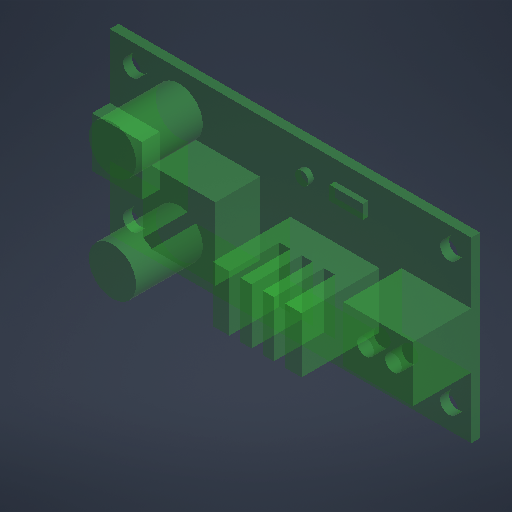
# Autodesk Inventor part: Power_Supply_Module
Saved by Autodesk Inventor 2027.1 (Build 311270010, 270A)
## iProperties
Part Number: Power_Supply_Module
Material: Generic
Document SubType Name: Modeling
Designer: austin
Appearance: Green
Author: austin
Autodesk Inventor part; units mm, degrees
sketch "Sketch1" plane through (0, 0, 0) normal (0, 0, 1) x (1, 0, 0)
  line L0 (-32.5, -16) -> (32.5, -16)
  line L1 (32.5, -16) -> (32.5, 16)
  line L2 (32.5, 16) -> (-32.5, 16)
  line L3 (-32.5, 16) -> (-32.5, -16)
  constraints: 8 end point, 2 parallel, 1 horizontal, 1 perpendicular
extrude "Extrusion1" add sketch "Sketch1" along normal blind 1.6
sketch "Sketch2" plane through (0, 0, 0) normal (0, 0, 1) x (1, 0, 0)
  circle A0 centre (-28.5, -12) radius 1.6
  circle A1 centre (28.5, -12) radius 1.6
  circle A2 centre (-28.5, 12) radius 1.6
  circle A3 centre (28.5, 12) radius 1.6
  constraints: 4 centre point
extrude "Extrusion2" cut sketch "Sketch2" along normal blind 2
ref_plane "Work Plane1" through (0, 0, 1.6) normal (0, 0, 1) x (1, 0, 0)
sketch "Sketch3" plane through (0, 0, 1.6) normal (0, 0, 1) x (1, 0, 0)
  line L0 (-32.5, -4.5) -> (-23.5, -4.5)
  line L1 (-23.5, -4.5) -> (-23.5, 4.5)
  line L2 (-23.5, 4.5) -> (-32.5, 4.5)
  line L3 (-32.5, 4.5) -> (-32.5, -4.5)
  constraints: 8 end point, 2 parallel, 1 horizontal, 1 perpendicular
extrude "Extrusion3" add sketch "Sketch3" along normal blind 3.2
sketch "Sketch4" plane through (0, 0, 1.6) normal (0, 0, 1) x (1, 0, 0)
  line L0 (-18.5, -6.5) -> (-5.5, -6.5)
  line L1 (-5.5, -6.5) -> (-5.5, 6.5)
  line L2 (-5.5, 6.5) -> (-18.5, 6.5)
  line L3 (-18.5, 6.5) -> (-18.5, -6.5)
  constraints: 8 end point, 2 parallel, 1 horizontal, 1 perpendicular
extrude "Extrusion4" add sketch "Sketch4" along normal blind 8
sketch "Sketch5" plane through (0, 0, 1.6) normal (0, 0, 1) x (1, 0, 0)
  circle A0 centre (-20, -9.5) radius 4.25
  circle A1 centre (-20, 9.5) radius 4.25
  constraints: 2 centre point
extrude "Extrusion5" add sketch "Sketch5" along normal blind 12
sketch "Sketch6" plane through (0, 0, 1.6) normal (0, 0, 1) x (1, 0, 0)
  line L0 (0, -7) -> (16, -7)
  line L1 (16, -7) -> (16, 3)
  line L2 (16, 3) -> (0, 3)
  line L3 (0, 3) -> (0, -7)
  constraints: 8 end point, 2 parallel, 1 horizontal, 1 perpendicular
extrude "Extrusion6" add sketch "Sketch6" along normal blind 14
ref_plane "Work Plane2" through (0, 0, 15.6) normal (0, 0, 1) x (1, 0, 0)
sketch "Sketch7" plane through (0, 0, 15.6) normal (0, 0, 1) x (1, 0, 0)
  line L0 (3, -7) -> (5, -7)
  line L1 (5, -7) -> (5, 3)
  line L2 (5, 3) -> (3, 3)
  line L3 (3, 3) -> (3, -7)
  line L4 (7, -7) -> (9, -7)
  line L5 (9, -7) -> (9, 3)
  line L6 (9, 3) -> (7, 3)
  line L7 (7, 3) -> (7, -7)
  line L8 (11, -7) -> (13, -7)
  line L9 (13, -7) -> (13, 3)
  line L10 (13, 3) -> (11, 3)
  line L11 (11, 3) -> (11, -7)
  constraints: 24 end point, 6 parallel, 3 horizontal, 3 perpendicular
extrude "Extrusion7" cut sketch "Sketch7" against normal blind 9
sketch "Sketch8" plane through (0, 0, 1.6) normal (0, 0, 1) x (1, 0, 0)
  line L0 (20, -5) -> (32.5, -5)
  line L1 (32.5, -5) -> (32.5, 5)
  line L2 (32.5, 5) -> (20, 5)
  line L3 (20, 5) -> (20, -5)
  constraints: 8 end point, 2 parallel, 1 horizontal, 1 perpendicular
extrude "Extrusion8" add sketch "Sketch8" along normal blind 10.5
ref_plane "Work Plane3" through (0, 0, 12.1) normal (0, 0, 1) x (1, 0, 0)
sketch "Sketch9" plane through (0, 0, 12.1) normal (0, 0, 1) x (1, 0, 0)
  circle A0 centre (24, 0) radius 1.5
  circle A1 centre (29, 0) radius 1.5
  constraints: 2 centre point
extrude "Extrusion9" cut sketch "Sketch9" against normal blind 3
sketch "Sketch10" plane through (0, 0, 1.6) normal (0, 0, 1) x (1, 0, 0)
  circle A0 centre (3, 11) radius 1.2
  line L0 (8, 10) -> (14, 10)
  line L1 (14, 10) -> (14, 12.5)
  line L2 (14, 12.5) -> (8, 12.5)
  line L3 (8, 12.5) -> (8, 10)
  constraints: 8 end point, 2 parallel, 1 centre point, 1 horizontal, 1 perpendicular
extrude "Extrusion10" add sketch "Sketch10" along normal blind 1
body "Solid1"
